Autodesk Fusion 360 part; units mm, degrees
(part 9 of 9)
equation "d1401 = abs(mountCircle / ( 2 * sqrt(2) ))"
equation "d1402 = driverPort"
equation "d1403 = abs(-mountCircle / ( 2 * sqrt(2) ))"
equation "d1404 = abs(-mountCircle / ( 2 * sqrt(2) ))"
equation "d1405 = driverPort"
equation "d1406 = abs(mountCircle / ( 2 * sqrt(2) ))"
equation "d1407 = abs(-mountCircle / ( 2 * sqrt(2) ))"
equation "d1408 = driverPort"
equation "d1409 = -( bodyLength )"
equation "d1451 = abs(55 mm)"
equation "d1452 = abs(66.5 mm)"
equation "d1453 = abs(130 mm)"
equation "d1454 = abs(66.5 mm)"
equation "d1455 = abs(130 mm)"
equation "d1456 = abs(75 mm)"
equation "d1457 = abs(55 mm)"
equation "d1458 = abs(75 mm)"
named bodies: "A Housing print", "B Moving Body print"
